Three-Point Connector native (Autodesk Fusion 360 design; units mm, degrees)
part number: 2026-10-13-21-21-55-140
Autodesk Fusion 360 part; units mm, degrees
ref_plane "WorkPlane1" through (0, 6.1, 0) normal (0, 1, 0) x (0, 0, 1)
sketch "Profile" plane through (0, 6.1, 0) normal (0, 1, 0) x (1, 0, 0)
  line L0 (65.2449, -27.5046) -> (9.7546, -27.5046)
  arc A0 (-3.25, -14.5) -> (9.7546, -27.5046) centre (9.7546, -14.5) ccw
  arc A1 (3.25, -14.5) -> (-3.25, -14.5) centre (0, -14.5) ccw
  arc A2 (3.25, -14.5) -> (9.7546, -21.0046) centre (9.7546, -14.5) ccw
  line L1 (9.7546, -21.0046) -> (29.4996, -21.0046)
  arc A3 (29.4996, -21.0046) -> (33.4998, -17.0044) centre (29.4996, -17.0044) ccw
  line L2 (33.4998, -17.0044) -> (33.4998, -14.4493)
  arc A4 (41.5001, -14.4493) -> (33.4998, -14.4493) centre (37.5, -14.4493) ccw
  line L3 (41.5001, -14.4493) -> (41.5001, -17.0049)
  arc A5 (41.5001, -17.0049) -> (45.4998, -21.0046) centre (45.4998, -17.0049) ccw
  line L4 (45.4998, -21.0046) -> (65.2449, -21.0046)
  arc A6 (65.2449, -21.0046) -> (71.7495, -14.5) centre (65.2449, -14.5) ccw
  arc A7 (78.2495, -14.4999) -> (71.7495, -14.5) centre (74.9995, -14.4999) ccw
  arc A8 (65.2449, -27.5046) -> (78.2495, -14.4999) centre (65.2449, -14.5) ccw
  dimension "d17" = 13.0046
  dimension "d18" = 3.25
  dimension "d19" = 4.0002
  dimension "d20" = 3.9997
  dimension "d21" = 9.7546
  dimension "d22" = 14.5
  dimension "d23" = 29.4996
  dimension "d24" = 14.4493
  dimension "d25" = 17.0049
  dimension "d26" = 65.2449
  dimension "d27" = 74.9995
  constraint horizontal L0
  constraint horizontal L1
  constraint vertical L2
  constraint vertical L3
  constraint horizontal L4
  constraint tangent L0 A8
  constraint tangent L0 A0
  constraint tangent A0 A1
  constraint tangent A1 A2
  constraint tangent A2 L1
  constraint tangent L1 A3
  constraint tangent A3 L2
  constraint tangent L2 A4
  constraint tangent A4 L3
  constraint tangent L3 A5
  constraint tangent A5 L4
  constraint tangent L4 A6
  constraint tangent A6 A7
  constraint tangent A7 A8
  constraint coincident A0.centre A2.centre
  constraint equal A3 A4
  constraint equal A2 A6
  constraint equal A1 A7
  constraint equal A0 A8
  constraint vertical origin A1.centre
  measures "d17" radius of A0
  measures "d18" radius of A1
  measures "d19" radius of A3
  measures "d20" radius of A5
  measures "d21" horizontal distance of origin A0.centre
  measures "d22" vertical distance of origin A0.centre
  measures "d23" horizontal distance of origin A3.centre
  measures "d24" vertical distance of origin A4.centre
  measures "d25" vertical distance of origin A5.centre
  measures "d26" horizontal distance of origin A6.centre
  measures "d27" horizontal distance of origin A7.centre
extrude "Profile (1)" add sketch "Profile" along normal mid plane 2
ref_plane "WorkPlane2" through (0, 6.1, 0) normal (0, 1, 0) x (0, 0, 1)
sketch "Hole 1" plane through (0, 6.1, 0) normal (0, 1, 0) x (1, 0, 0)
  circle A0 centre (37.4998, -14.4493) radius 1.75
  dimension "d28" = 3.5
  dimension "d29" = 37.4998
  dimension "d30" = 14.4493
  measures "d28" diameter of A0
  measures "d29" horizontal distance of origin A0.centre
  measures "d30" vertical distance of origin A0.centre
extrude "Hole 1 (1)" cut sketch "Hole 1" along normal mid plane 2
ref_plane "WorkPlane3" through (0, 6.1, 0) normal (0, 1, 0) x (0, 0, 1)
sketch "Hole 2" plane through (0, 6.1, 0) normal (0, 1, 0) x (1, 0, 0)
  circle A0 centre (0, -14.5) radius 1.75
  dimension "d31" = 3.5
  dimension "d32" = 14.5
  constraint vertical origin A0.centre
  measures "d31" diameter of A0
  measures "d32" vertical distance of origin A0.centre
extrude "Hole 2 (1)" cut sketch "Hole 2" along normal mid plane 2
ref_plane "WorkPlane4" through (0, 6.1, 0) normal (0, 1, 0) x (0, 0, 1)
sketch "Hole 3" plane through (0, 6.1, 0) normal (0, 1, 0) x (1, 0, 0)
  circle A0 centre (74.9995, -14.5) radius 1.75
  dimension "d33" = 3.5
  dimension "d34" = 74.9995
  dimension "d35" = 14.5
  measures "d33" diameter of A0
  measures "d34" horizontal distance of origin A0.centre
  measures "d35" vertical distance of origin A0.centre
extrude "Hole 3 (1)" cut sketch "Hole 3" along normal mid plane 2
named bodies: "Three-Point Connector native"
